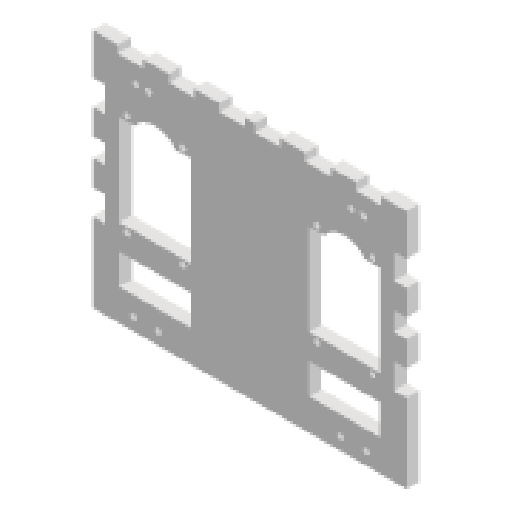
# Autodesk Inventor part: MainBottom
Saved by Autodesk Inventor 2025.2 (Build 292293000, 293)
## iProperties
Created: 2025-06-21
Part Number: MainBottom
Material: Generic
Document SubType Name: Modeling
Designer: ricoa
Density: 1 g/cm^3
Appearance: Default
Author: ricoa
Autodesk Inventor part; units mm, degrees
ref_plane "YZ Plane" through (0, 0, 0) normal (1, 0, 0) x (0, 1, 0)
ref_plane "XZ Plane" through (0, 0, 0) normal (0, 1, 0) x (-1, 0, 0)
ref_plane "XY Plane" through (0, 0, 0) normal (0, 0, 1) x (1, 0, 0)
sketch "Sketch1" plane through (0, 0, 0) normal (0, 0, 1) x (1, 0, 0)
  line L0 (0, 0) -> (0, 55.5) construction
  line L1 (0, 0) -> (47.5, 0) construction
  line L2 (0, 0) -> (30, 0)
  line L3 (-63, 0) -> (-58, 0)
  line L4 (61.6631, 6.5682) -> (61.6079, 26.0682) projected
  line L5 (56.5739, 38.115) -> (18.574, 38.0076) construction
  line L6 (-25.25, -15.25) -> (-49.75, -15.25) construction
  line L7 (25.25, -15.25) -> (49.75, -15.25) construction
  line L8 (-49.75, 31.25) -> (-41.5, 31.25) construction
  line L9 (37.5, -15.25) -> (37.5, -23.25)
  line L10 (54.6012, 28.4448) -> (54.596, 30.2984) projected
  line L11 (-54.6388, 28.3683) -> (-54.6418, 30.2219) projected
  line L12 (-54.5989, 4.0755) -> (-54.6388, 28.3683) projected
  line L13 (-20.6388, 28.4241) -> (-20.6254, 20.2777) projected
  line L14 (54.6012, 28.4448) -> (54.596, 30.2984) projected
  line L15 (54.6699, 4.152) -> (54.6012, 28.4448) projected
  circle A0 centre (37.5, 20) radius 9.75 projected
  circle A1 centre (45.5, 20) radius 0.75 projected
  circle A2 centre (37.5, 12) radius 0.75 projected
  circle A3 centre (29.5, 20) radius 0.75 projected
  circle A4 centre (37.5, 28) radius 0.75 projected
  circle A5 centre (37.5, 20) radius 4.75 projected
  circle A6 centre (43.1569, 25.6569) radius 0.75 projected
  circle A7 centre (31.8431, 25.6569) radius 0.75 projected
  circle A8 centre (31.8431, 14.3431) radius 0.75 projected
  circle A9 centre (43.1569, 14.3431) radius 0.75 projected
  line L16 (56.6631, 6.5541) -> (56.608, 26.054) projected
  line L17 (20.647, 12.2023) -> (20.67, 4.0559) projected
  line L18 (0, 0) -> (57, 0)
  line L19 (57, 0) -> (62, 0)
  line L20 (41.5, 31.25) -> (33.5, 31.25) projected
  line L21 (-41.5, 31.25) -> (-33.5, 31.25) projected
  line L22 (0, 0) -> (0, 31.25)
  line L23 (0, 31.25) -> (0, 39.25)
  line L24 (0, 39.25) -> (0, 44.25)
  line L25 (0, 31.25) -> (0, -23.25)
  line L26 (0, 0) -> (-62, 0)
  line L27 (62, 44.25) -> (-62, 44.25)
  line L28 (-62, 44.25) -> (-62, -23.25)
  line L29 (-62, -23.25) -> (62, -23.25)
  line L30 (62, -23.25) -> (62, 44.25)
  dimension "d57" = 8
  dimension "d58" = 57
  dimension "d59" = 5
  dimension "d60" = 8
  dimension "d61" = 5
  dimension "d62" = 62
  constraints: 32 end point, 7 point on line, 2 horizontal, 2 parallel, 1 midpoint, 1 perpendicular, 1 vertical
  measures "d57" distance of L9.start L9.end
  measures "d58" distance of L18.start L18.end
  measures "d59" distance of L18.end L19.end
  measures "d60" distance of L22.end L23.end
  measures "d61" distance of L23.end L24.end
  measures "d62" distance of L18.start L26.end
extrude "Extrusion1" add sketch "Sketch1" along normal blind 5 contours L22 L23 L24 L27 L30 L19 L18 L2 | L26 L3 L28 L27 L24 L23 L22 | L2 L18 L19 L30 L29 L25 | L25 L29 L28 L3 L26
sketch "Sketch2" plane through (0, 0, 0) normal (0, 0, -1) x (-1, 0, 0)
  line L0 (0, 0) -> (-37.5, 0)
  line L1 (-37.5, 20) -> (-48.5, 20) construction
  line L2 (-48.5, 20) -> (-48.5, 28)
  circle A0 centre (-48.5, 28) radius 1.25
  circle A1 centre (-26.5, 28) radius 1.25
  circle A2 centre (-37.5, 20) radius 10
  line L3 (-37.5, 20) -> (-37.5, 0)
  line L4 (-26.5, 28) -> (-48.5, 28) construction
  line L5 (0, 0) -> (0, 46.0375)
  circle A3 centre (-26.5, -12) radius 1.25
  circle A4 centre (-48.5, -12) radius 1.25
  line L6 (-26.5, -12) -> (-26.5, 28) construction
  line L7 (-26.5, -12) -> (-48.5, -12) construction
  line L8 (-48.5, -12) -> (-48.5, 28) construction
  line L9 (37.5, 20) -> (48.5, 20) construction
  line L10 (48.5, 20) -> (48.5, 28)
  circle A5 centre (48.5, 28) radius 1.25
  circle A6 centre (26.5, 28) radius 1.25
  circle A7 centre (37.5, 20) radius 10
  line L11 (37.5, 20) -> (37.5, 0)
  line L12 (26.5, 28) -> (48.5, 28) construction
  circle A8 centre (26.5, -12) radius 1.25
  circle A9 centre (48.5, -12) radius 1.25
  line L13 (26.5, -12) -> (26.5, 28) construction
  line L14 (26.5, -12) -> (48.5, -12) construction
  line L15 (48.5, -12) -> (48.5, 28) construction
  dimension "d30" = 37.5
  dimension "d32" = 11
  dimension "d33" = 8
  dimension "d34" = 2.5
  dimension "d35" = 20
  dimension "d38" = 20
  dimension "d39" = 2.5
  dimension "d40" = 2.5
  dimension "d41" = 40
  constraints: 32 end point, 10 centre point, 9 symmetric about line, 4 coincident, 3 horizontal, 3 vertical, 2 perpendicular, 5 other
  measures "d30" distance of L0.start L0.end
  measures "d32" distance of L1.start L1.end
  measures "d33" distance of L1.end L2.end
  measures "d34" diameter of A0
  measures "d35" diameter of A2
  measures "d38" distance of L3.start L0.end
  measures "d39" diameter of A3
  measures "d40" diameter of A4
  measures "d41" distance of L4.start L6.start
extrude "Extrusion2" cut sketch "Sketch2" against normal blind 5
sketch "Sketch4" plane through (0, 0, 0) normal (0, 0, -1) x (-1, 0, 0)
  circle A0 centre (37.5, 20) radius 10 projected
  circle A1 centre (48.5, -12) radius 1.25 projected
  circle A2 centre (-48.5, 28) radius 1.25 projected
  circle A3 centre (26.5, -12) radius 1.25 projected
  circle A4 centre (-48.5, -12) radius 1.25 projected
  circle A5 centre (48.5, 28) radius 1.25 projected
  circle A6 centre (-26.5, 28) radius 1.25 projected
  circle A7 centre (-37.5, 20) radius 10 projected
  circle A8 centre (26.5, 28) radius 1.25 projected
  circle A9 centre (-26.5, -12) radius 1.25 projected
  line L0 (62, -23.25) -> (-62, -23.25) projected
  line L1 (62, 44.25) -> (62, -23.25) projected
  line L2 (-62, 44.25) -> (62, 44.25) projected
  line L3 (-62, -23.25) -> (-62, 44.25) projected
  line L4 (-62, 44.25) -> (62, 44.25) projected
  line L5 (62, 44.25) -> (52, 44.25)
  line L6 (52, 44.25) -> (52, 39.25)
  line L7 (52, 39.25) -> (42, 39.25)
  line L8 (42, 39.25) -> (42, 44.25)
  line L9 (42, 44.25) -> (32, 44.25)
  line L10 (32, 44.25) -> (32, 39.25)
  line L11 (32, 39.25) -> (22, 39.25)
  line L12 (22, 39.25) -> (22, 44.25)
  line L13 (22, 44.25) -> (12, 44.25)
  line L14 (12, 44.25) -> (12, 39.25)
  line L15 (12, 39.25) -> (2, 39.25)
  line L16 (2, 39.25) -> (2, 44.25)
  line L17 (0, 0) -> (0, 44.25) construction
  line L18 (0, 0) -> (-62, 0) construction
  line L19 (-52, 44.25) -> (-52, 39.25)
  line L20 (-52, 39.25) -> (-42, 39.25)
  line L21 (-42, 39.25) -> (-42, 44.25)
  line L22 (-42, 44.25) -> (-32, 44.25)
  line L23 (-32, 44.25) -> (-32, 39.25)
  line L24 (-32, 39.25) -> (-22, 39.25)
  line L25 (-22, 39.25) -> (-22, 44.25)
  line L26 (-22, 44.25) -> (-12, 44.25)
  line L27 (-12, 44.25) -> (-12, 39.25)
  line L28 (-12, 39.25) -> (-2, 39.25)
  line L29 (-2, 39.25) -> (-2, 44.25)
  line L30 (-62, 44.25) -> (-62, 34.25) construction
  line L31 (-62, 34.25) -> (-57, 34.25)
  line L32 (-57, 34.25) -> (-57, 24.25)
  line L33 (-57, 24.25) -> (-62, 24.25)
  line L34 (-62, -23.25) -> (-62, -13.25)
  line L35 (-62, -13.25) -> (-57, -13.25)
  line L36 (-57, -13.25) -> (-57, -3.25)
  line L37 (-57, -3.25) -> (-62, -3.25)
  line L38 (-62, 24.25) -> (-62, 14.25)
  line L39 (-62, 14.25) -> (-57, 14.25)
  line L40 (-57, 14.25) -> (-57, 6.75)
  line L41 (-57, 6.75) -> (-62, 6.75)
  line L42 (62, 34.25) -> (57, 34.25)
  line L43 (57, 34.25) -> (57, 24.25)
  line L44 (57, 24.25) -> (62, 24.25)
  line L45 (62, -13.25) -> (57, -13.25)
  line L46 (57, -13.25) -> (57, -3.25)
  line L47 (57, -3.25) -> (62, -3.25)
  line L48 (62, 24.25) -> (62, 14.25)
  line L49 (62, 14.25) -> (57, 14.25)
  line L50 (57, 14.25) -> (57, 6.75)
  line L51 (57, 6.75) -> (62, 6.75)
  point P0 (62, 0)
  dimension "d63" = 10
  dimension "d64" = 5
  dimension "d65" = 10
  dimension "d66" = 10
  dimension "d67" = 10
  dimension "d68" = 10
  dimension "d69" = 10
  dimension "d70" = 10
  dimension "d71" = 5
  dimension "d72" = 10
  dimension "d73" = 10
  dimension "d74" = 10
  dimension "d75" = 10
  dimension "d76" = 7.5
  constraints: 94 end point, 25 symmetric about line, 10 point on line, 8 perpendicular, 4 horizontal, 4 vertical, 16 other
  measures "d63" distance of L1.start L5.end
  measures "d64" distance of L5.end L6.end
  measures "d65" distance of L6.end L7.end
  measures "d66" distance of L8.end L9.end
  measures "d67" distance of L10.end L11.end
  measures "d68" distance of L12.end L13.end
  measures "d69" distance of L14.end L15.end
  measures "d70" distance of L2.start L30.end
  measures "d71" distance of L30.end L31.end
  measures "d72" distance of L31.end L32.end
  measures "d73" distance of L0.end L34.end
  measures "d74" distance of L35.end L36.end
  measures "d75" distance of L33.end L38.end
  measures "d76" distance of L39.end L40.end
extrude "Extrusion4" cut sketch "Sketch4" against normal blind 5 contours L45 L46 L47 L1 | L3 L37 L36 L35 | L51 L50 L49 L1 | L3 L39 L40 L41 | L44 L43 L42 L1 | L3 L31 L32 L33 | L6 L7 L8 L2 | L2 L21 L20 L19 | L10 L11 L12 L2 | L2 L25 L24 L23 | L14 L15 L16 L2 | L2 L29 L28 L27
sketch "Sketch5" plane through (0, 0, 5) normal (0, 0, 1) x (1, 0, 0)
  line L0 (-29, -20.25) -> (-59, -20.25) projected
  line L1 (-29, -20.25) -> (-29, -16.25) projected
  line L2 (-29, -16.25) -> (-59, -16.25) projected
  line L3 (-59, -20.25) -> (-59, -16.25) projected
  circle A0 centre (-46, -18.25) radius 1.25 projected
  circle A1 centre (-36, -18.25) radius 1.25 projected
  line L4 (59, -16.25) -> (29, -16.25) projected
  line L5 (29, -16.25) -> (29, -20.25) projected
  line L6 (59, -20.25) -> (29, -20.25) projected
  line L7 (59, -16.25) -> (59, -20.25) projected
  circle A2 centre (46, -18.25) radius 1.25 projected
  circle A3 centre (36, -18.25) radius 1.25 projected
  line L8 (-59, 32.25) -> (-34, 32.25) projected
  line L9 (-34, 32.25) -> (-34, 41.25) projected
  line L10 (-59, 41.25) -> (-34, 41.25) projected
  line L11 (-59, 32.25) -> (-59, 41.25) projected
  circle A4 centre (-45, 34.25) radius 1.25 projected
  circle A5 centre (-40, 34.25) radius 1.25 projected
  line L12 (34, 41.25) -> (59, 41.25) projected
  line L13 (34, 41.25) -> (34, 32.25) projected
  line L14 (34, 32.25) -> (59, 32.25) projected
  line L15 (59, 41.25) -> (59, 32.25) projected
  circle A6 centre (45, 34.25) radius 1.25 projected
  circle A7 centre (40, 34.25) radius 1.25 projected
  point P0 (0, 0)
  point P1 (-29, 41.25)
  point P2 (29, 41.25)
extrude "Extrusion5" cut sketch "Sketch5" against normal blind 10 contours A0 | A1 | A2 | A3 | A4 | A5 | A6 | A7
move faces "Move1" translate (0, 6.25, 0) faces at (-55.3333, 44.25, 1.6667) (-45.3333, 39.25, 1.6667) (-35.3333, 44.25, 1.6667) (-25.3333, 39.25, 1.6667) (-15.3333, 44.25, 1.6667) (-5.3333, 39.25, 1.6667) (0.6667, 44.25, 1.6667) (8.6667, 39.25, 1.6667) (18.6667, 44.25, 1.6667) (28.6667, 39.25, 1.6667) (38.6667, 44.25, 1.6667) (48.6667, 39.25, 1.6667) (58.6667, 44.25, 1.6667) (-52, 40.9167, 1.6667) (-32, 40.9167, 1.6667) (-12, 40.9167, 1.6667) (22, 40.9167, 1.6667) (42, 40.9167, 1.6667) (62, 37.5833, 1.6667) (-62, 40.9167, 1.6667) (-42, 42.5833, 1.6667) (-22, 42.5833, 1.6667) (-2, 42.5833, 1.6667) (12, 42.5833, 1.6667) (32, 42.5833, 1.6667) (52, 42.5833, 1.6667)
move faces "Move2" translate (0, 6.25, 0) faces at (-45.3478, 35.4506, 1.6667) (-40.3478, 35.4506, 1.6667) (44.6522, 35.4506, 1.6667) (39.6522, 35.4506, 1.6667)
move faces "Move3" translate (0, -21.25, 0) faces at (45.6522, -17.0494, 1.6667) (37.2338, -18.4505, 1.6667) (-34.7662, -18.4505, 1.6667) (-46.3478, -17.0494, 1.6667) (-20.6667, -23.25, 1.6667)
sketch "Sketch8" plane through (0, 0, 0) normal (0, 0, -1) x (-1, 0, 0)
  line L0 (49.6464, 31) -> (25.3536, 31) projected
  line L1 (51.5, 29.1464) -> (49.6464, 31) projected
  line L2 (51.5, -13.1464) -> (51.5, 29.1464) projected
  line L3 (49.6464, -15) -> (51.5, -13.1464) projected
  line L4 (25.3536, -15) -> (49.6464, -15) projected
  line L5 (23.5, -13.1464) -> (25.3536, -15) projected
  line L6 (23.5, 29.1464) -> (23.5, -13.1464) projected
  line L7 (25.3536, 31) -> (23.5, 29.1464) projected
  line L8 (28.5, -10) -> (46.5, -10)
  line L9 (46.5, -10) -> (46.5, 26)
  line L10 (46.5, 26) -> (28.5, 26)
  line L11 (28.5, 26) -> (28.5, -10)
  line L12 (28.5, 26) -> (23.5, 26)
  line L13 (46.5, 26) -> (51.5, 26)
  line L14 (46.5, -10) -> (51.5, -10)
  line L15 (28.5, -10) -> (23.5, -10)
  line L16 (0, 0) -> (0, 60.325)
  line L17 (23.5, -10) -> (23.5, -20) construction
  line L18 (23.5, -20) -> (23.5, -32)
  line L19 (23.5, -32) -> (51.5, -32)
  line L20 (51.5, -32) -> (51.5, -20)
  line L21 (51.5, -20) -> (23.5, -20)
  line L22 (-49.6464, 31) -> (-25.3536, 31)
  line L23 (-51.5, 29.1464) -> (-49.6464, 31)
  line L24 (-51.5, -13.1464) -> (-51.5, 29.1464)
  line L25 (-49.6464, -15) -> (-51.5, -13.1464)
  line L26 (-25.3536, -15) -> (-49.6464, -15)
  line L27 (-23.5, -13.1464) -> (-25.3536, -15)
  line L28 (-23.5, 29.1464) -> (-23.5, -13.1464)
  line L29 (-25.3536, 31) -> (-23.5, 29.1464)
  line L30 (-28.5, -10) -> (-46.5, -10)
  line L31 (-46.5, -10) -> (-46.5, 26)
  line L32 (-46.5, 26) -> (-28.5, 26)
  line L33 (-28.5, 26) -> (-28.5, -10)
  line L34 (-28.5, 26) -> (-23.5, 26)
  line L35 (-46.5, 26) -> (-51.5, 26)
  line L36 (-46.5, -10) -> (-51.5, -10)
  line L37 (-28.5, -10) -> (-23.5, -10)
  line L38 (-23.5, -10) -> (-23.5, -20) construction
  line L39 (-23.5, -20) -> (-23.5, -32)
  line L40 (-23.5, -32) -> (-51.5, -32)
  line L41 (-51.5, -32) -> (-51.5, -20)
  line L42 (-51.5, -20) -> (-23.5, -20)
  dimension "d90" = 5
  dimension "d91" = 10
  dimension "d92" = 12
  constraints: 70 end point, 20 symmetric about line, 18 point on line, 4 perpendicular, 1 vertical, 3 other
  measures "d90" distance between parallel lines of L6 L11
  measures "d91" distance of L15.end L17.end
  measures "d92" distance of L17.end L18.end
extrude "Extrusion6" cut sketch "Sketch8" against normal blind 10 contours L2 L14 L9 L13 | L12 L11 L15 L6 | L9 L8 L11 L10 | L21 L20 L19 L18 | L35 L31 L36 L24 | L28 L37 L33 L34 | L32 L33 L30 L31 | L39 L40 L41 L42
sketch "Sketch9" plane through (0, 0, 0) normal (0, 0, -1) x (-1, 0, 0)
  line L0 (51.5, -20) -> (51.5, -32) projected
  line L1 (51.5, -32) -> (23.5, -32) projected
  line L2 (23.5, -32) -> (23.5, -20) projected
  line L3 (23.5, -20) -> (51.5, -20) projected
  line L4 (-23.5, -20) -> (-23.5, -32) projected
  line L5 (-23.5, -32) -> (-51.5, -32) projected
  line L6 (-51.5, -32) -> (-51.5, -20) projected
  line L7 (-51.5, -20) -> (-23.5, -20) projected
  circle A0 centre (-40, 40.5) radius 1.25 projected
  circle A1 centre (36, -39.5) radius 1.25 projected
  circle A2 centre (-36, -39.5) radius 1.25 projected
  circle A3 centre (40, 40.5) radius 1.25 projected
  circle A4 centre (-45, 40.5) radius 1.25 projected
  circle A5 centre (46, -39.5) radius 1.25 projected
  circle A6 centre (-46, -39.5) radius 1.25 projected
  circle A7 centre (45, 40.5) radius 1.25 projected
  line L8 (62, 6.75) -> (57, 6.75) projected
  line L9 (57, 6.75) -> (57, 14.25) projected
  line L10 (57, 14.25) -> (62, 14.25) projected
  line L11 (62, 24.25) -> (62, 14.25) projected
  line L12 (62, 24.25) -> (57, 24.25) projected
  line L13 (57, 24.25) -> (57, 34.25) projected
  line L14 (57, 34.25) -> (62, 34.25) projected
  line L15 (62, 50.5) -> (62, 34.25) projected
  line L16 (52, 50.5) -> (62, 50.5) projected
  line L17 (52, 50.5) -> (52, 45.5) projected
  line L18 (52, 45.5) -> (42, 45.5) projected
  line L19 (42, 45.5) -> (42, 50.5) projected
  line L20 (32, 50.5) -> (42, 50.5) projected
  line L21 (32, 50.5) -> (32, 45.5) projected
  line L22 (32, 45.5) -> (22, 45.5) projected
  line L23 (22, 45.5) -> (22, 50.5) projected
  line L24 (12, 50.5) -> (22, 50.5) projected
  line L25 (12, 50.5) -> (12, 45.5) projected
  line L26 (12, 45.5) -> (2, 45.5) projected
  line L27 (2, 45.5) -> (2, 50.5) projected
  line L28 (-2, 50.5) -> (2, 50.5) projected
  line L29 (-2, 50.5) -> (-2, 45.5) projected
  line L30 (-2, 45.5) -> (-12, 45.5) projected
  line L31 (-12, 45.5) -> (-12, 50.5) projected
  line L32 (-22, 50.5) -> (-12, 50.5) projected
  line L33 (-22, 50.5) -> (-22, 45.5) projected
  line L34 (-22, 45.5) -> (-32, 45.5) projected
  line L35 (-32, 45.5) -> (-32, 50.5) projected
  line L36 (-42, 50.5) -> (-32, 50.5) projected
  line L37 (-42, 50.5) -> (-42, 45.5) projected
  line L38 (-42, 45.5) -> (-52, 45.5) projected
  line L39 (-52, 45.5) -> (-52, 50.5) projected
  line L40 (-62, 50.5) -> (-52, 50.5) projected
  line L41 (-62, 34.25) -> (-62, 50.5) projected
  line L42 (-62, 34.25) -> (-57, 34.25) projected
  line L43 (-57, 34.25) -> (-57, 24.25) projected
  line L44 (-57, 24.25) -> (-62, 24.25) projected
  line L45 (-62, 14.25) -> (-62, 24.25) projected
  line L46 (-62, 14.25) -> (-57, 14.25) projected
  line L47 (-57, 14.25) -> (-57, 6.75) projected
  line L48 (-57, 6.75) -> (-62, 6.75) projected
  line L49 (-62, -3.25) -> (-62, 6.75) projected
  line L50 (-62, -3.25) -> (-57, -3.25) projected
  line L51 (-57, -3.25) -> (-57, -13.25) projected
  line L52 (-57, -13.25) -> (-62, -13.25) projected
  line L53 (-62, -44.5) -> (-62, -13.25) projected
  line L54 (62, -44.5) -> (-62, -44.5) projected
  line L55 (62, -13.25) -> (62, -44.5) projected
  line L56 (62, -13.25) -> (57, -13.25) projected
  line L57 (57, -13.25) -> (57, -3.25) projected
  line L58 (57, -3.25) -> (62, -3.25) projected
  line L59 (62, 6.75) -> (62, -3.25) projected
  circle A8 centre (-26.5, -12) radius 1.25 projected
  circle A9 centre (26.5, 28) radius 1.25 projected
  line L60 (-29.5, 26) -> (-23.5, 26) projected
  line L61 (-23.5, 26) -> (-23.5, -10) projected
  line L62 (-23.5, -10) -> (-51.5, -10) projected
  line L63 (-51.5, -10) -> (-51.5, 26) projected
  line L64 (-51.5, 26) -> (-45.5, 26) projected
  arc A10 (-29.5, 26) -> (-45.5, 26) centre (-37.5, 20) ccw projected
  circle A11 centre (-26.5, 28) radius 1.25 projected
  circle A12 centre (48.5, 28) radius 1.25 projected
  circle A13 centre (-48.5, -12) radius 1.25 projected
  circle A14 centre (26.5, -12) radius 1.25 projected
  circle A15 centre (-48.5, 28) radius 1.25 projected
  circle A16 centre (48.5, -12) radius 1.25 projected
  line L65 (45.5, 26) -> (51.5, 26) projected
  line L66 (51.5, 26) -> (51.5, -10) projected
  line L67 (51.5, -10) -> (23.5, -10) projected
  line L68 (23.5, -10) -> (23.5, 26) projected
  line L69 (23.5, 26) -> (29.5, 26) projected
  arc A17 (45.5, 26) -> (29.5, 26) centre (37.5, 20) ccw projected
  line L70 (62, 47.5) -> (-62, 47.5) projected
  point P0 (0, 0)
  point P1 (-42, 47.5)
  point P2 (-52, 47.5)
  point P3 (-22, 47.5)
  point P4 (-32, 47.5)
  point P5 (52, 47.5)
  point P6 (42, 47.5)
  point P7 (32, 47.5)
  point P8 (22, 47.5)
  point P9 (12, 47.5)
  point P10 (2, 47.5)
  point P11 (-2, 47.5)
  point P12 (-12, 47.5)
extrude "Extrusion7" add sketch "Sketch9" against normal blind 5 contours L17 L18 L19 L70 | L21 L22 L23 L70 | L25 L26 L27 L70 | L29 L30 L31 L70 | L33 L34 L35 L70 | L37 L38 L39 L70
equation "\"d77\" = d64"
body "Solid1"
